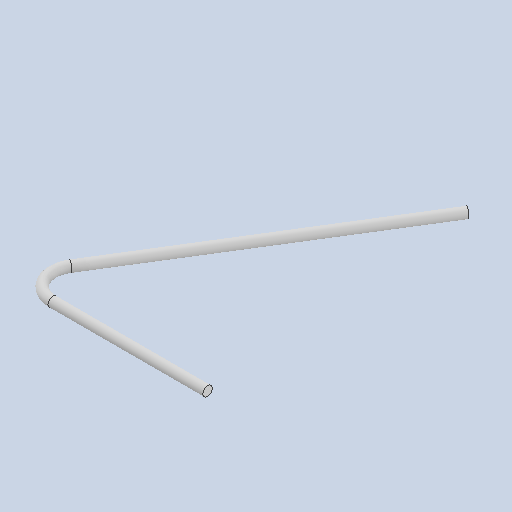
# Autodesk Inventor part: wire2_1
Saved by Autodesk Inventor 2026.1 (Build 301233020, 233B)
## iProperties
Created: 2025-11-30
Part Number: wire2_1
Material: Generico
Document SubType Name: Modeling
Designer: maxbu
Density: 1 g/cm^3
Appearance: Default
Author: maxbu
Autodesk Inventor part; units mm, degrees
ref_plane "YZ Plane" through (0, 0, 0) normal (1, 0, 0) x (0, 1, 0)
ref_plane "XZ Plane" through (0, 0, 0) normal (0, 1, 0) x (-1, 0, 0)
ref_plane "XY Plane" through (0, 0, 0) normal (0, 0, 1) x (1, 0, 0)
sketch "Schizzo1" plane through (0, 0, 0) normal (0, 1, 0) x (-1, 0, 0)
  line L0 (0, 0) -> (24, 0)
  line L1 (24, 0) -> (24, -4) construction
  line L2 (24, -4) -> (27.3996, -6.1078) construction
  line L3 (27.3996, -6.1078) -> (3.8386, -44.1078)
  arc A0 (27.3996, -6.1078) -> (24, 0) centre (24, -4) ccw
  dimension "d0" = 58.2
  dimension "d1" = 4
  dimension "d2" = 24
  dimension "d3" = 38
  constraints: 8 end point, 2 point on circle, 1 centre point, 1 coincident, 1 equal length, 1 horizontal, 1 perpendicular, 1 vertical
  measures "d0" angle of L0 L3
  measures "d1" distance of L0.end L1.end
  measures "d2" distance of L0.start L0.end
  measures "d3" vertical distance of L2.end L3.end
sketch "Schizzo2" plane through (0, 0, 0) normal (1, 0, 0) x (0, 1, 0)
  circle A0 centre (0, 0) radius 0.75
  dimension "d4" = 1.5
  constraints: 1 centre point, 1 coincident
  measures "d4" diameter of A0
sweep "Sweep1" add profiles "Schizzo2" path "Schizzo1"
